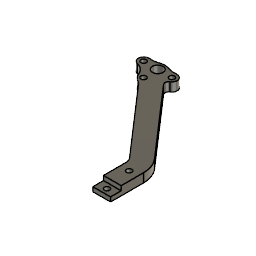
5mm cut parts (Autodesk Fusion 360 archive; units mm, degrees)
design "arm"
part number: 2026-08-28-11-39-51-718
Autodesk Fusion 360 part; units mm, degrees
sketch "Sketch1" plane through (0, 0, 0) normal (0, 0, 1) x (1, 0, 0)
  line L0 (-5, -3) -> (-5, 17.5)
  line L1 (-5, 17.5) -> (-48.0297, 67)
  line L2 (-48.0297, 67) -> (-34.7796, 67)
  line L3 (-34.7796, 67) -> (5, 21.2388)
  line L4 (5, 21.2388) -> (5, -3)
  line L5 (5, -3) -> (-5, -3)
  dimension "d1" = 10
  dimension "d2" = 5
  dimension "d3" = 10
  dimension "d4" = 20.5
  dimension "d5" = 139
  dimension "d6" = 3
  dimension "d7" = 67
  constraint vertical L0
  constraint perpendicular L0 L2
  constraint perpendicular L2 L4
  constraint perpendicular L0 L5
  constraint parallel L1 L3
  measures "d1" distance of L0 L4
  measures "d2" horizontal distance of origin L0.start
  measures "d3" distance of L1 L3
  measures "d4" distance of L0.start L0.end
  measures "d5" angle of L0 L1
  measures "d6" distance of origin L5
  measures "d7" vertical distance of origin L1.end
extrude "Extrude1" add sketch "Sketch1" along normal blind 5
sketch "Sketch2" plane through (0, 0, 5) normal (0, 0, 1) x (-1, 0, 0)
  line L0 (-5, 3) -> (-5, -21.2388)
  line L1 (-5, -21.2388) -> (34.7796, -67)
  line L2 (34.7796, -67) -> (48.0297, -67)
  line L3 (48.0297, -67) -> (5, -17.5)
  line L4 (5, -17.5) -> (5, 3)
  line L5 (5, 3) -> (-5, 3)
  line L6 (5, 3) -> (-5, 3)
  line L7 (-5, 3) -> (-5, -3)
  line L8 (-5, -3) -> (5, -3)
  line L9 (5, -3) -> (5, 3)
  dimension "d10" = 6
  constraint horizontal L6
  constraint vertical L7
  constraint horizontal L8
  constraint vertical L9
  constraint coincident L0 L7.end
  constraint coincident L4.end L5.start
  measures "d10" distance of L6 L8
extrude "Extrude2" cut sketch "Sketch2" against normal blind 2.5 contours L0 L4 L5 L6 L7 L8 L9
sketch "Sketch3" plane through (0, 0, 5) normal (0, 0, 1) x (-1, 0, 0)
  line L0 (5, -3) -> (-5, -3)
  line L1 (-5, -3) -> (-5, -21.2388)
  line L2 (-5, -21.2388) -> (34.7796, -67)
  line L3 (34.7796, -67) -> (48.0297, -67)
  line L4 (48.0297, -67) -> (5, -17.5)
  line L5 (5, -17.5) -> (5, -3)
  circle A0 centre (0, 0) radius 1.5
  circle A1 centre (0, -12.5) radius 1.5
  dimension "d13" = 3
  dimension "d14" = 3
  dimension "d15" = 12.5
  constraint coincident A0.centre origin
  constraint vertical A0.centre A1.centre
  measures "d13" diameter of A0
  measures "d14" diameter of A1
  measures "d15" distance of A0.centre A1.centre
extrude "Extrude3" cut sketch "Sketch3" against normal through all contours A0 | A1
sketch "Sketch4" plane through (0, 0, 5) normal (0, 0, 1) x (-1, 0, 0)
  circle A0 centre (0, -12.5) radius 1.5
  line L0 (5, -3) -> (-5, -3)
  line L1 (-5, -3) -> (-5, -21.2388)
  line L2 (-5, -21.2388) -> (34.7796, -67)
  line L3 (34.7796, -67) -> (48.0297, -67)
  line L4 (48.0297, -67) -> (5, -17.5)
  line L5 (5, -17.5) -> (5, -3)
  line L6 (48.0297, -67) -> (49.4046, -67)
  arc A1 (49.4046, -73) -> (49.4046, -67) centre (49.4046, -70) ccw
  line L7 (49.4046, -73) -> (33.4046, -73)
  arc A2 (33.4046, -67) -> (33.4046, -73) centre (33.4046, -70) ccw
  line L8 (33.4046, -67) -> (34.7796, -67)
  dimension "d17" = 6
  dimension "d18" = 16
  constraint coincident L3.end L4.start
  constraint parallel L3 L6
  constraint tangent L6 A1
  constraint parallel L6 L7
  constraint tangent L7 A2
  constraint coincident L2.end L3.start
  constraint parallel L3 L8
  constraint vertical L6.end A1.start
  constraint vertical L7.end A2.start
  constraint equal L6 L8
  measures "d17" distance of L7 L8
  measures "d18" distance of A1.centre A2.centre
extrude "Extrude4" add sketch "Sketch4" against normal blind 5 contours L3 L6 A1 L7 A2 L8
hole "Hole1" at (-49.4046, 70, 5) at (-33.4046, 70, 5) direction (0, 0, -1) diameter 3 end through all
sketch "Sketch5" plane through (0, 0, 5) normal (0, 0, 1) x (-1, 0, 0)
  circle A0 centre (49.4046, -70) radius 1.5
  circle A1 centre (33.4046, -70) radius 1.5
  circle A2 centre (0, -12.5) radius 1.5
  line L0 (5, -3) -> (-5, -3)
  line L1 (-5, -3) -> (-5, -21.2388)
  line L2 (-5, -21.2388) -> (34.7796, -67)
  line L3 (34.7796, -67) -> (33.4046, -67)
  arc A3 (33.4046, -67) -> (33.4046, -73) centre (33.4046, -70) ccw
  line L4 (33.4046, -73) -> (49.4046, -73)
  arc A4 (49.4046, -73) -> (49.4046, -67) centre (49.4046, -70) ccw
  line L5 (49.4046, -67) -> (48.0297, -67)
  line L6 (48.0297, -67) -> (5, -17.5)
  line L7 (5, -17.5) -> (5, -3)
  circle A5 centre (41.4046, -62) radius 1.5
  dimension "d23" = 3
  dimension "d24" = 8
  dimension "d25" = 8
  measures "d23" diameter of A5
  measures "d24" horizontal distance of A0.centre A5.centre
  measures "d25" vertical distance of A1.centre A5.centre
extrude "Extrude5" cut sketch "Sketch5" against normal blind 6 contours A5
sketch "Sketch6" plane through (0, 0, 5) normal (0, 0, 1) x (-1, 0, 0)
  circle A0 centre (41.4046, -62) radius 1.5
  circle A1 centre (49.4046, -70) radius 1.5
  circle A2 centre (33.4046, -70) radius 1.5
  circle A3 centre (0, -12.5) radius 1.5
  line L0 (5, -3) -> (-5, -3)
  line L1 (-5, -3) -> (-5, -21.2388)
  line L2 (-5, -21.2388) -> (34.7796, -67)
  line L3 (34.7796, -67) -> (33.4046, -67)
  arc A4 (33.4046, -67) -> (33.4046, -73) centre (33.4046, -70) ccw
  line L4 (33.4046, -73) -> (49.4046, -73)
  arc A5 (49.4046, -73) -> (49.4046, -67) centre (49.4046, -70) ccw
  line L5 (49.4046, -67) -> (48.0297, -67)
  line L6 (48.0297, -67) -> (5, -17.5)
  line L7 (5, -17.5) -> (5, -3)
  arc A6 (44.9987, -63.5133) -> (40.4063, -58.2303) centre (37.2733, -65.5913) ccw
  line L8 (41.4046, -62) -> (35.9177, -66.7697)
  dimension "d28" = 7
  dimension "d29" = 8
  constraint coincident L6 A6.end
  constraint coincident L6 A6.start
  constraint coincident A0.centre L8.start
  constraint perpendicular L2 L8
  constraint coincident A6.centre L8
  measures "d28" distance of A6.start A6.end
  measures "d29" radius of A6
extrude "Extrude6" add sketch "Sketch6" against normal blind 5 contours L6 A6
sketch "Sketch7" plane through (0, 0, 5) normal (0, 0, 1) x (-1, 0, 0)
  circle A0 centre (41.4046, -62) radius 1.5
  circle A1 centre (49.4046, -70) radius 1.5
  circle A2 centre (33.4046, -70) radius 1.5
  circle A3 centre (0, -12.5) radius 1.5
  line L0 (5, -3) -> (-5, -3)
  line L1 (-5, -3) -> (-5, -21.2388)
  line L2 (-5, -21.2388) -> (34.7796, -67)
  line L3 (34.7796, -67) -> (33.4046, -67)
  arc A4 (33.4046, -67) -> (33.4046, -73) centre (33.4046, -70) ccw
  line L4 (33.4046, -73) -> (49.4046, -73)
  arc A5 (49.4046, -73) -> (49.4046, -67) centre (49.4046, -70) ccw
  line L5 (49.4046, -67) -> (48.0297, -67)
  line L6 (48.0297, -67) -> (44.9987, -63.5133)
  arc A6 (44.9987, -63.5133) -> (40.4063, -58.2303) centre (37.2733, -65.5913) ccw
  line L7 (40.4063, -58.2303) -> (5, -17.5)
  line L8 (5, -17.5) -> (5, -3)
  circle A7 centre (41.4046, -70) radius 3
  dimension "d32" = 6
  constraint horizontal A1.centre A7.centre
  constraint vertical A0.centre A7.centre
  measures "d32" diameter of A7
extrude "Extrude7" cut sketch "Sketch7" against normal blind 5.5 contours A7
sketch "Sketch8" plane through (0, 0, 5) normal (0, 0, 1) x (-1, 0, 0)
  line L0 (5, -3) -> (-5, -3)
  line L1 (-5, -3) -> (-5, -21.2388)
  line L2 (-5, -21.2388) -> (34.7796, -67)
  line L3 (34.7796, -67) -> (33.4046, -67)
  arc A0 (33.4046, -67) -> (33.4046, -73) centre (33.4046, -70) ccw
  line L4 (33.4046, -73) -> (41.4046, -73)
  circle A1 centre (41.4046, -70) radius 3
  line L5 (41.4046, -73) -> (49.4046, -73)
  arc A2 (49.4046, -73) -> (49.4046, -67) centre (49.4046, -70) ccw
  line L6 (49.4046, -67) -> (48.0297, -67)
  line L7 (48.0297, -67) -> (44.9987, -63.5133)
  arc A3 (44.9987, -63.5133) -> (40.4063, -58.2303) centre (37.2733, -65.5913) ccw
  line L8 (40.4063, -58.2303) -> (5, -17.5)
  line L9 (5, -17.5) -> (5, -3)
  circle A4 centre (0, -12.5) radius 1.5
  circle A5 centre (33.4046, -70) radius 1.5
  circle A6 centre (49.4046, -70) radius 1.5
  circle A7 centre (41.4046, -62) radius 1.5
  arc A8 (37.4046, -73) -> (45.4046, -73) centre (41.4046, -66.0718) ccw
  dimension "d35" = 8
  dimension "d36" = 4
  dimension "d37" = 8
  constraint coincident L4 A8.start
  constraint coincident L5 A8.end
  measures "d35" distance of A8.end A8.start
  measures "d36" horizontal distance of A1.centre A8.end
  measures "d37" radius of A8
extrude "Extrude8" add sketch "Sketch8" against normal blind 5 contours L4 L5 A8
fillet "Fillet1" radius 7 1 edges at (-48.0297, 67, 2.5)
fillet "Fillet2" radius 10 2 edges at (-45.4046, 73, 2.5) (-37.4046, 73, 2.5)
fillet "Fillet3" radius 2 1 edges at (-34.7796, 67, 2.5)
fillet "Fillet4" radius 5 2 edges at (-44.9987, 63.5133, 2.5) (-40.4063, 58.2303, 2.5)
fillet "Fillet5" radius 5 1 edges at (-5, 17.5, 2.5)
fillet "Fillet6" radius 15 1 edges at (5, 21.2388, 2.5)
equation "d4 = ( 35 / 2 ) * 1 mm + 3 mm"
equation "d15 = ( 25 / 2 ) * 1 mm"
